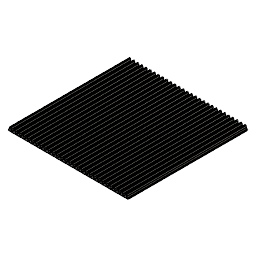
Insubark Panel (Autodesk Fusion 360 design; units mm, degrees)
part number: 2026-04-13-14-19-06-178
Autodesk Fusion 360 part; units mm, degrees
sketch "Sketch2" plane through (0, 0, 0) normal (0, 0, 1) x (1, 0, 0)
  line L0 (0, 0) -> (600, 0)
  line L1 (600, 0) -> (600, 600)
  line L2 (600, 600) -> (0, 600)
  line L3 (0, 600) -> (0, 0)
  dimension "d1" = 600
  dimension "d2" = 600
  constraint horizontal L0
  constraint vertical L1
  constraint horizontal L2
  constraint vertical L3
  constraint coincident L0.start L3.end
  measures "d1" distance of L0.start L0.end
  measures "d2" distance of L0.start L2.end
extrude "Extrude1" add sketch "Sketch2" along normal blind 5
sketch "Sketch3" plane through (0, 0, 0) normal (0, 1, 0) x (1, 0, 0)
sketch "Sketch4" plane through (0, 0, 0) normal (0, -1, 0) x (1, 0, 0)
  line L0 (0, 0) -> (600, 0)
  line L1 (600, 0) -> (600, 5)
  line L2 (600, 5) -> (0, 5)
  line L3 (0, 5) -> (0, 0)
  line L4 (29.6224, 20) -> (29.327, 20)
  line L5 (26.3483, 17.3566) -> (24.8691, 5)
  line L6 (32.5871, 17.459) -> (34.5162, 5)
  arc A0 (32.5871, 17.459) -> (29.6224, 20) centre (29.6224, 17) ccw
  arc A1 (29.327, 20) -> (26.3483, 17.3566) centre (29.327, 17) ccw
  dimension "d6" = 3
  constraint horizontal L4
  constraint coincident L2 L5.end
  constraint coincident L2 L6.end
  constraint tangent L4 A0
  constraint tangent L6 A0
  constraint tangent L4 A1
  constraint tangent L5 A1
  constraint equal A0 A1
  measures "d6" radius of A0
extrude "Extrude2" add sketch "Sketch4" against normal blind 600 contours L2 L4 L5 L6 A0 A1
fillet "Fillet1" radius 5 2 edges at (24.8691, 300, 5) (34.5162, 300, 5)
pattern_linear "R-Pattern1" count 28 spacing 20.7407 along (1, 0, 0) of "Extrude2"
fillet "Fillet2" radius 5 4 edges at (45.6098, 300, 5) (55.257, 300, 5) (66.3506, 300, 5) (75.9977, 300, 5)
pattern_linear "R-Pattern2" count 2 spacing 20.5 along (-1, 0, 0) of "Extrude2"
fillet "Fillet3" radius 5 2 edges at (4.3691, 300, 5) (14.0162, 300, 5)
fillet "Fillet4" radius 5 6 edges at (87.0913, 300, 5) (96.7385, 300, 5) (107.832, 300, 5) (117.4792, 300, 5) (128.5728, 300, 5) (138.2199, 300, 5)
fillet "Fillet5" radius 5 7 edges at (149.3135, 300, 5) (158.9607, 300, 5) (170.0543, 300, 5) (179.7014, 300, 5) (190.795, 300, 5) (200.4422, 300, 5) (211.5358, 300, 5)
fillet "Fillet6" radius 5 7 edges at (221.1829, 300, 5) (232.2765, 300, 5) (241.9236, 300, 5) (253.0172, 300, 5) (262.6644, 300, 5) (273.758, 300, 5) (283.4051, 300, 5)
fillet "Fillet7" radius 5 5 edges at (294.4987, 300, 5) (304.1459, 300, 5) (315.2395, 300, 5) (324.8866, 300, 5) (335.9802, 300, 5)
fillet "Fillet8" radius 5 6 edges at (345.6273, 300, 5) (356.7209, 300, 5) (366.3681, 300, 5) (377.4617, 300, 5) (387.1088, 300, 5) (398.2024, 300, 5)
fillet "Fillet9" radius 5 19 edges at (407.8496, 300, 5) (418.9432, 300, 5) (428.5903, 300, 5) (439.6839, 300, 5) (449.3311, 300, 5) (460.4246, 300, 5) (470.0718, 300, 5) (481.1654, 300, 5) (490.8125, 300, 5) (501.9061, 300, 5) (511.5533, 300, 5) (522.6469, 300, 5) (532.294, 300, 5) (543.3876, 300, 5) (553.0348, 300, 5) (564.1283, 300, 5) (573.7755, 300, 5) (584.8691, 300, 5) (594.5162, 300, 5)
